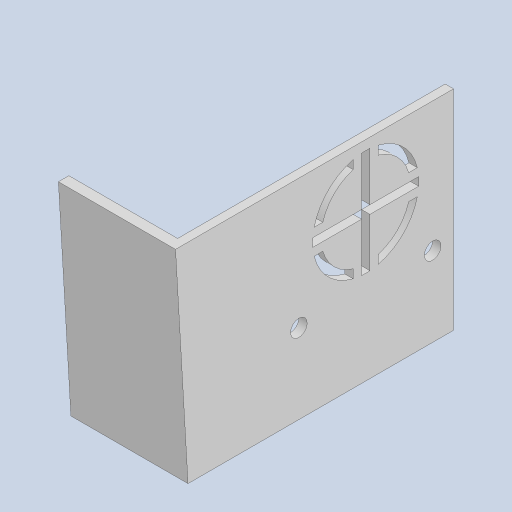
# Autodesk Inventor part: template_for_gate_02
Saved by Autodesk Inventor 2024.4 (Build 284460030, 460C)
## iProperties
Created: 2026-09-23
Part Number: template_for_gate_02
Material: Generic
Document SubType Name: Modeling
Designer: tooles01
Density: 1 g/cm^3
Appearance: Default
Author: tooles01
Autodesk Inventor part; units mm, degrees
ref_plane "YZ Plane" through (0, 0, 0) normal (1, 0, 0) x (0, 1, 0)
ref_plane "XZ Plane" through (0, 0, 0) normal (0, 1, 0) x (-1, 0, 0)
ref_plane "XY Plane" through (0, 0, 0) normal (0, 0, 1) x (1, 0, 0)
sketch "Sketch1" plane through (0, 0, 0) normal (1, 0, 0) x (0, 1, 0)
  line L0 (50, 45.4881) -> (0, 42.5)
  line L1 (0, 42.5) -> (0, 40)
  line L2 (0, 40) -> (50, 42.9881)
  line L3 (50, 42.9881) -> (50, 45.4881)
  line L4 (-10, 0) -> (60, 0) construction
  point P0 (0, 0)
  dimension "cage_wall_angle" = 3.42
  dimension "d18" = 2.5
  dimension "d21" = 40
  dimension "d22" = 50
  constraints: 8 end point, 2 vertical, 1 parallel, 1 vertical alignment
  measures "cage_wall_angle" angle of L4 L2
  measures "d18" distance of L0.end L1.end
  measures "d21" distance of point (0, 0) L1.end
  measures "d22" horizontal distance of L0.start L0.end
sketch "Sketch2" plane through (0, 0, 0) normal (1, 0, 0) x (0, 1, 0)
  circle A0 centre (35, 0) radius 12.7
  circle A1 centre (19, 16) radius 2
  circle A2 centre (19, -16) radius 2
  line L0 (19, 16) -> (19, -16) construction
  line L1 (50, 40) -> (0, 40)
  line L2 (0, 40) -> (0, -21)
  line L3 (0, -21) -> (50, -21)
  line L4 (50, -21) -> (50, 40)
  line L5 (0, 40) -> (50, 42.9881) construction
  line L6 (50, 42.9881) -> (0, 40)
  line L7 (0, 40) -> (0, 40)
  line L8 (50, 40) -> (50, 42.9881)
  line L9 (47.6606, -1) -> (36, -1)
  line L10 (47.6606, 1) -> (36, 1)
  line L11 (36, -1) -> (36, -12.6606)
  line L12 (34, -12.6606) -> (34, -1)
  line L13 (36, 12.6606) -> (36, 1)
  line L14 (34, 12.6606) -> (34, 1)
  line L15 (34, -1) -> (22.3394, -1)
  line L16 (34, 1) -> (22.3394, 1)
  line L17 (35, 1) -> (35, -1) construction
  line L18 (36, 0) -> (34, 0) construction
  circle A3 centre (35, 0) radius 10.7
  line L19 (47.3406, 3) -> (45.2708, 3)
  line L20 (24.7292, -3) -> (22.6594, -3)
  line L21 (30.7574, 4.2426) -> (39.2426, -4.2426) construction
  line L22 (45.2708, -3) -> (47.3406, -3)
  line L23 (38, -10.2708) -> (38, -12.3406)
  line L24 (24.7292, 3) -> (22.6594, 3)
  line L25 (32, 10.2708) -> (32, 12.3406)
  line L26 (39.2426, 4.2426) -> (30.7574, -4.2426) construction
  line L27 (32, -10.2708) -> (32, -12.3406)
  line L28 (38, 10.2708) -> (38, 12.3406)
  point P0 (0, 0)
  point P1 (19, 0)
  point P2 (24.3468, 1)
  point P3 (0, 40)
  point P4 (34, 10.6532)
  point P5 (24.3468, -1)
  point P6 (34, -10.6532)
  point P7 (36, 10.6532)
  point P8 (45.6532, 1)
  point P9 (45.6532, -1)
  point P10 (36, -10.6532)
  dimension "d0" = 25.4
  dimension "d29" = 2
  dimension "d1" = 4
  dimension "d2" = 32
  dimension "d3" = 16
  dimension "d4" = 19
  dimension "d5" = 35
  dimension "d12" = 15
  dimension "d23" = 5
  dimension "d24" = 50
  dimension "spacing" = 2
  dimension "d26" = 2
  dimension "d27" = 40
  dimension "d33" = 12
  dimension "d34" = 45
  dimension "d35" = 12
  dimension "d37" = 2
  dimension "d38" = 2
  dimension "d39" = 2
  dimension "d40" = 2
  constraints: 56 end point, 11 collinear, 8 vertical, 6 horizontal, 5 coincident, 5 midpoint, 5 point on line, 4 perpendicular, 2 centre point, 2 horizontal alignment, 1 equal radius, 31 other
  measures "d1" diameter of A1
  measures "d2" distance of L0.start L0.end
  measures "d3" distance from line of L0 point (35, 0)
  measures "d4" distance from line of L2 A1.centre
  measures "d5" distance from line of L2 point (35, 0)
  measures "d12" distance from line of L4 point (35, 0)
  measures "d23" distance from line of L3 A2.centre
  measures "d24" distance of L2.end L3.end
  measures "spacing" distance between parallel lines of L9 L10
  measures "d26" distance between parallel lines of L14 L13
  measures "d27" distance from line of L1 point (35, 0)
  measures "d33" distance of L26.start L26.end
  measures "d34" angle of L26 L13
  measures "d35" distance of L21.start L21.end
  measures "d37" distance between parallel lines of L11 L23
  measures "d38" distance between parallel lines of L16 L24
  measures "d39" distance between parallel lines of L12 L27
  measures "d40" distance between parallel lines of L15 L20
extrude "Ex1" add sketch "Sketch1" against normal blind 28
extrude "Ex2" add sketch "Sketch2" against normal blind 2 contours L10 A3 L19 A0 | A0 L22 A3 L9 | L10 L13 A3 | A3 L11 L9 | L28 A3 L13 A0 | A0 L11 A3 L23 | L14 A3 L25 A0 | L14 L16 A3 | A0 L27 A3 L12 | A3 L15 L12 | L24 A3 L16 A0 | A0 L15 A3 L20 | L4 L3 L2 L1 | L1 L6 L8
equation "\"d29\" = spacing"
equation "\"d26\" = spacing"
body "Solid1"
